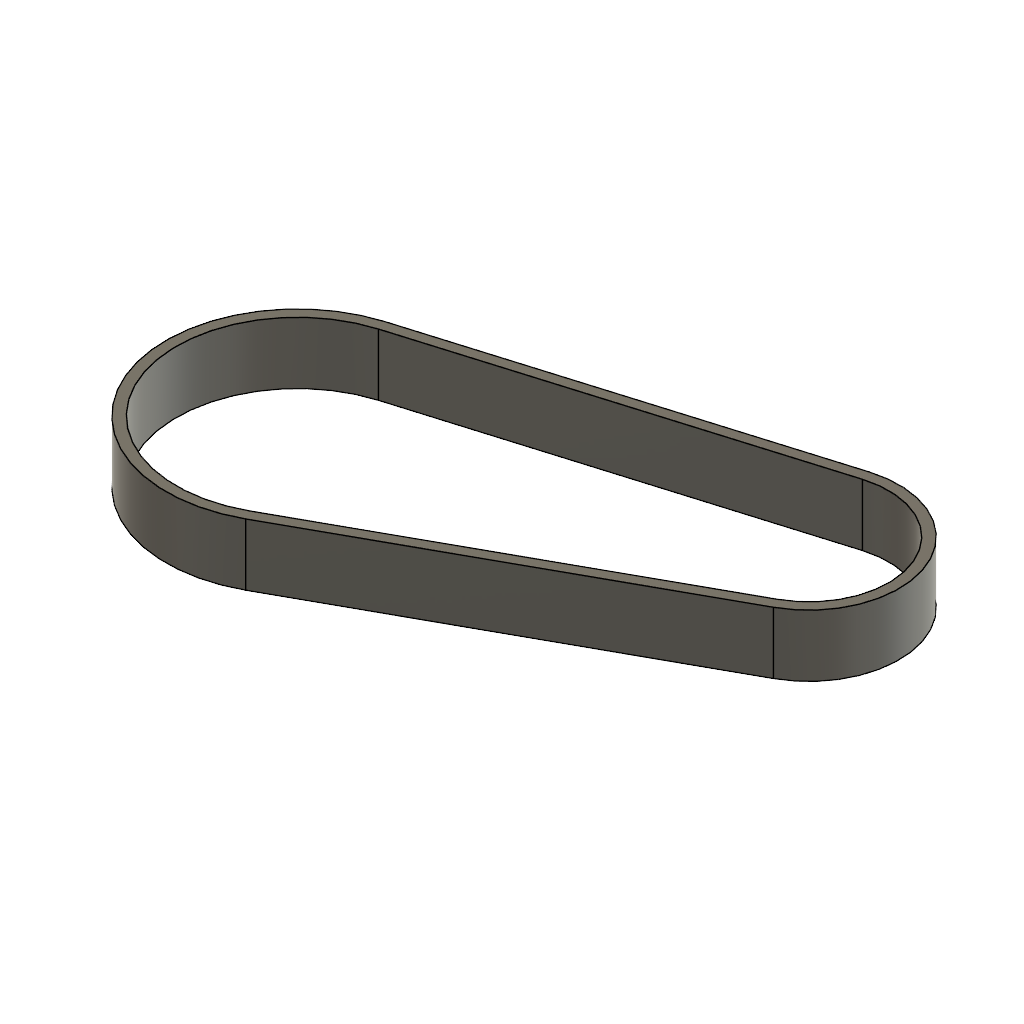
02-27_풀리벨트 (Autodesk Fusion 360 design; units mm, degrees)
Autodesk Fusion 360 part; units mm, degrees
sketch "스케치1" plane through (0, 0, 0) normal (0, 1, 0) x (1, 0, 0)
  line L0 (-33.6927, 7.2519) -> (2.459, 18.1213)
  line L1 (-23.8733, -16.1277) -> (9.1978, 2.0764)
  arc A0 (-33.6927, 7.2519) -> (-23.8733, -16.1277) centre (-30.0216, -4.9581) ccw
  arc A1 (9.1978, 2.0764) -> (2.459, 18.1213) centre (4.9784, 9.7419) ccw
  dimension "d1" = 17.5
  dimension "d2" = 25.5
  dimension "d3" = 35
  dimension "d4" = 14.7
  constraint tangent L1 A1
  constraint tangent L0 A0
  constraint tangent L1 A0
  constraint tangent L0 A1
  measures "d1" diameter of A1
  measures "d2" diameter of A0
  measures "d3" horizontal distance of A1.centre A0.centre
  measures "d4" vertical distance of A1.centre A0.centre
extrude "돌출1" add sketch "스케치1" along normal blind 6
sketch "스케치2" plane through (0, 6, 0) normal (0, 1, 0) x (-1, 0, 0)
  arc A0 (33.6927, -7.2519) -> (23.8733, 16.1277) centre (30.0216, 4.9581) ccw
  line L0 (23.8733, 16.1277) -> (-9.1978, -2.0764)
  arc A1 (-9.1978, -2.0764) -> (-2.459, -18.1213) centre (-4.9784, -9.7419) ccw
  line L1 (-2.459, -18.1213) -> (33.6927, -7.2519)
  line L2 (33.4048, -6.2943) -> (-2.7469, -17.1637)
  line L3 (24.3555, 15.2517) -> (-8.7156, -2.9525)
  arc A2 (33.4048, -6.2943) -> (24.3555, 15.2517) centre (30.0216, 4.9581) ccw
  arc A3 (-8.7156, -2.9525) -> (-2.7469, -17.1637) centre (-4.9784, -9.7419) ccw
  dimension "d7" = 23.5
  dimension "d8" = 15.5
  constraint concentric A0 A2
  constraint concentric A1 A3
  constraint tangent L2 A3
  constraint tangent L3 A3
  constraint tangent L2 A2
  constraint tangent L3 A2
  measures "d7" diameter of A2
  measures "d8" diameter of A3
extrude "돌출2" cut sketch "스케치2" against normal blind 6 contours L2 L3 A2 A3
